Wall (Autodesk Fusion 360 design; units mm, degrees)
part number: 2026-10-17-17-11-49-669
Autodesk Fusion 360 part; units mm, degrees
sketch "Sketch1" plane through (0, 0, 0) normal (0, 0, 1) x (1, 0, 0)
  line L0 (500, 20) -> (-500, 20)
  line L1 (-500, 20) -> (-500, -20)
  line L2 (-500, -20) -> (500, -20)
  line L3 (500, -20) -> (500, 20)
  line L4 (500, 20) -> (-500, -20) construction
  line L5 (-500, 20) -> (500, -20) construction
  dimension "d1" = 1000
  dimension "d2" = 40
  constraint horizontal L0
  constraint perpendicular L0 L1
  constraint parallel L0 L2
  constraint parallel L1 L3
  constraint coincident L4 origin
  constraint coincident L5 origin
  measures "d1" distance of L1.end L2.end
  measures "d2" distance of L0.end L1.end
extrude "Extrude1" add sketch "Sketch1" along normal blind 2200
sketch "Sketch2" plane through (0, -20, 0) normal (0, -1, 0) x (1, 0, 0)
  line L0 (-500, 0) -> (500, 0)
  line L1 (500, 0) -> (500, 2200)
  line L2 (500, 2200) -> (-500, 2200)
  line L3 (-500, 2200) -> (-500, 0)
  line L4 (0, 0) -> (0, 2200) construction
  line L5 (460, 290) -> (-460, 290)
  line L6 (-460, 290) -> (-460, 250)
  line L7 (-460, 250) -> (460, 250)
  line L8 (460, 250) -> (460, 290)
  line L9 (460, 290) -> (-460, 250) construction
  line L10 (-460, 290) -> (460, 250) construction
  line L11 (460, 540) -> (-460, 540)
  line L12 (-460, 540) -> (-460, 500)
  line L13 (-460, 500) -> (460, 500)
  line L14 (460, 500) -> (460, 540)
  line L15 (460, 790) -> (-460, 790)
  line L16 (-460, 790) -> (-460, 750)
  line L17 (-460, 750) -> (460, 750)
  line L18 (460, 750) -> (460, 790)
  line L19 (460, 1040) -> (-460, 1040)
  line L20 (-460, 1040) -> (-460, 1000)
  line L21 (-460, 1000) -> (460, 1000)
  line L22 (460, 1000) -> (460, 1040)
  line L23 (460, 1290) -> (-460, 1290)
  line L24 (-460, 1290) -> (-460, 1250)
  line L25 (-460, 1250) -> (460, 1250)
  line L26 (460, 1250) -> (460, 1290)
  line L27 (460, 1540) -> (-460, 1540)
  line L28 (-460, 1540) -> (-460, 1500)
  line L29 (-460, 1500) -> (460, 1500)
  line L30 (460, 1500) -> (460, 1540)
  line L31 (460, 1790) -> (-460, 1790)
  line L32 (-460, 1790) -> (-460, 1750)
  line L33 (-460, 1750) -> (460, 1750)
  line L34 (460, 1750) -> (460, 1790)
  line L35 (460, 2040) -> (-460, 2040)
  line L36 (-460, 2040) -> (-460, 2000)
  line L37 (-460, 2000) -> (460, 2000)
  line L38 (460, 2000) -> (460, 2040)
  line L39 (460, 0) -> (460, 2200)
  line L40 (-460, 0) -> (-460, 2200)
  line L41 (-500, 2200) -> (500, 2200)
  line L42 (500, 2200) -> (500, 0)
  line L43 (500, 0) -> (-500, 0)
  line L44 (-500, 0) -> (-500, 2200)
  point P0 (0, 270)
  dimension "d8" = 920
  dimension "d9" = 40
  dimension "d10" = 250
  dimension "d14" = 0
  dimension "d15" = 250
  constraint coincident L4.start origin
  constraint midpoint L2 L4.end
  constraint horizontal L5
  constraint perpendicular L5 L6
  constraint parallel L5 L7
  constraint parallel L6 L8
  constraint coincident L9 P0
  constraint coincident L10 P0
  constraint coincident L4 P0
  constraint coincident L0 L39.start
  constraint coincident L2 L39.end
  constraint perpendicular L2 L39
  constraint coincident L0 L40.start
  constraint coincident L2 L40.end
  constraint perpendicular L2 L40
  constraint horizontal L41
  constraint vertical L42
  constraint horizontal L43
  constraint vertical L44
  constraint coincident L0.end L1.start
  constraint coincident L2.end L3.start
  measures "d8" distance of L6.end L7.end
  measures "d9" distance of L5.end L6.end
  measures "d10" distance of L0 L7
extrude "Extrude2" cut sketch "Sketch2" against normal up to surface (40 mm away) contours L0 L7 L39 L40 L43 | L2 L35 L39 L40 L41 | L5 L13 L39 L40 | L31 L37 L39 L40 | L11 L17 L39 L40 | L27 L33 L39 L40 | L15 L21 L39 L40 | L23 L29 L39 L40 | L19 L25 L39 L40
equation "wall_width = 1000 mm" comment "The entire width of the wall."
equation "rung_diameter = 4 cm"
equation "rung_width = wall_width - ( 2 * rung_diameter )" comment "The horizontal length of each rung"
equation "d8 = rung_width"
equation "d9 = rung_diameter"
equation "d10 = rung_spacing"
equation "rung_spacing = 0.25 m"
equation "d15 = rung_spacing"
